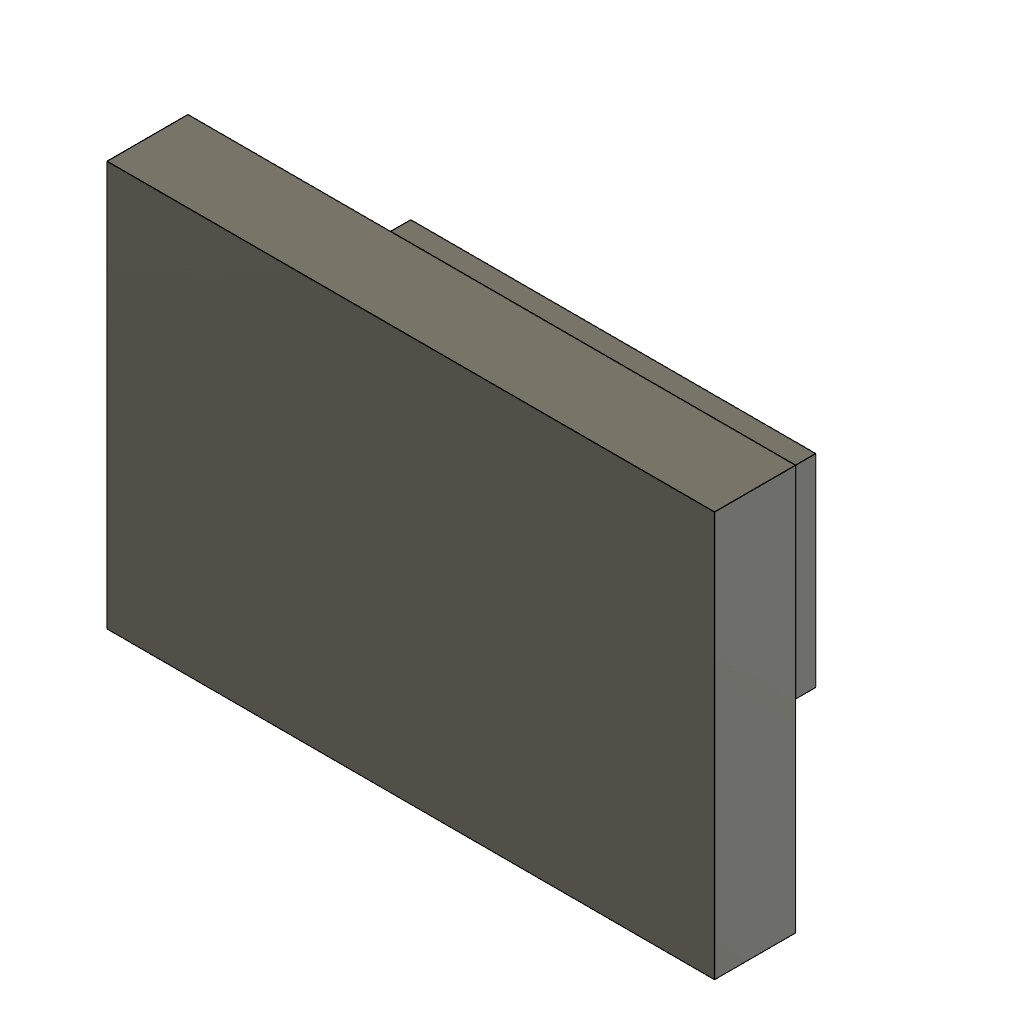
sk_on_offset_plane (Autodesk Fusion 360 design; units mm, degrees)
part number: 2026-11-13-14-35-51-912
Autodesk Fusion 360 part; units mm, degrees
sketch "Sketch1" plane through (0, 0, 0) normal (0, 0, 1) x (1, 0, 0)
  line L0 (0, 0) -> (30, 0)
  line L1 (30, 0) -> (30, 20)
  line L2 (30, 20) -> (0, 20)
  line L3 (0, 20) -> (0, 0)
extrude "Extrude1" add sketch "Sketch1" along normal blind 4
ref_plane "WorkPlane1" through (0, 0, -6) normal (0, 0, 1) x (1, 0, 0)
sketch "Sketch2" plane through (0, 0, -6) normal (0, 0, 1) x (1, 0, 0)
  line L0 (5, 5) -> (25, 5)
  line L1 (25, 5) -> (25, 15)
  line L2 (25, 15) -> (5, 15)
  line L3 (5, 15) -> (5, 5)
extrude "Extrude2" add sketch "Sketch2" along normal blind 6
